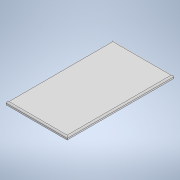
# Autodesk Inventor part: front_sertar_mijlociu
Saved by Autodesk Inventor 2022.6 (Build 266554000, 554)
## iProperties
Created: 2026-10-25
Part Number: front_sertar_mijlociu
Material: Generic
Document SubType Name: Modeling
Designer: Dragos Macovei
Density: 1 g/cm^3
Appearance: Default
Author: Dragos Macovei
Autodesk Inventor part; units mm, degrees
ref_plane "YZ Plane" through (0, 0, 0) normal (1, 0, 0) x (0, 1, 0)
ref_plane "XZ Plane" through (0, 0, 0) normal (0, 1, 0) x (-1, 0, 0)
ref_plane "XY Plane" through (0, 0, 0) normal (0, 0, 1) x (1, 0, 0)
sketch "Sketch1" plane through (0, 0, 0) normal (0, 1, 0) x (-1, 0, 0)
  line L0 (0, 0) -> (386, 0)
  line L1 (386, 0) -> (386, 675)
  line L2 (386, 675) -> (0, 675)
  line L3 (0, 675) -> (0, 0)
  dimension "d0" = 675
  dimension "d1" = 386
  constraints: 8 end point, 2 parallel, 1 horizontal, 1 perpendicular
  measures "d0" distance of L1.end L0.end
  measures "d1" distance of L1.end L2.end
extrude "Extrusion1" add sketch "Sketch1" along normal blind 18
fillet "Fillet1" radius 9 4 edges at (0, 18, 337.5) (-193, 18, 675) (-386, 18, 337.5) (-193, 18, 0)
body "Solid1"
